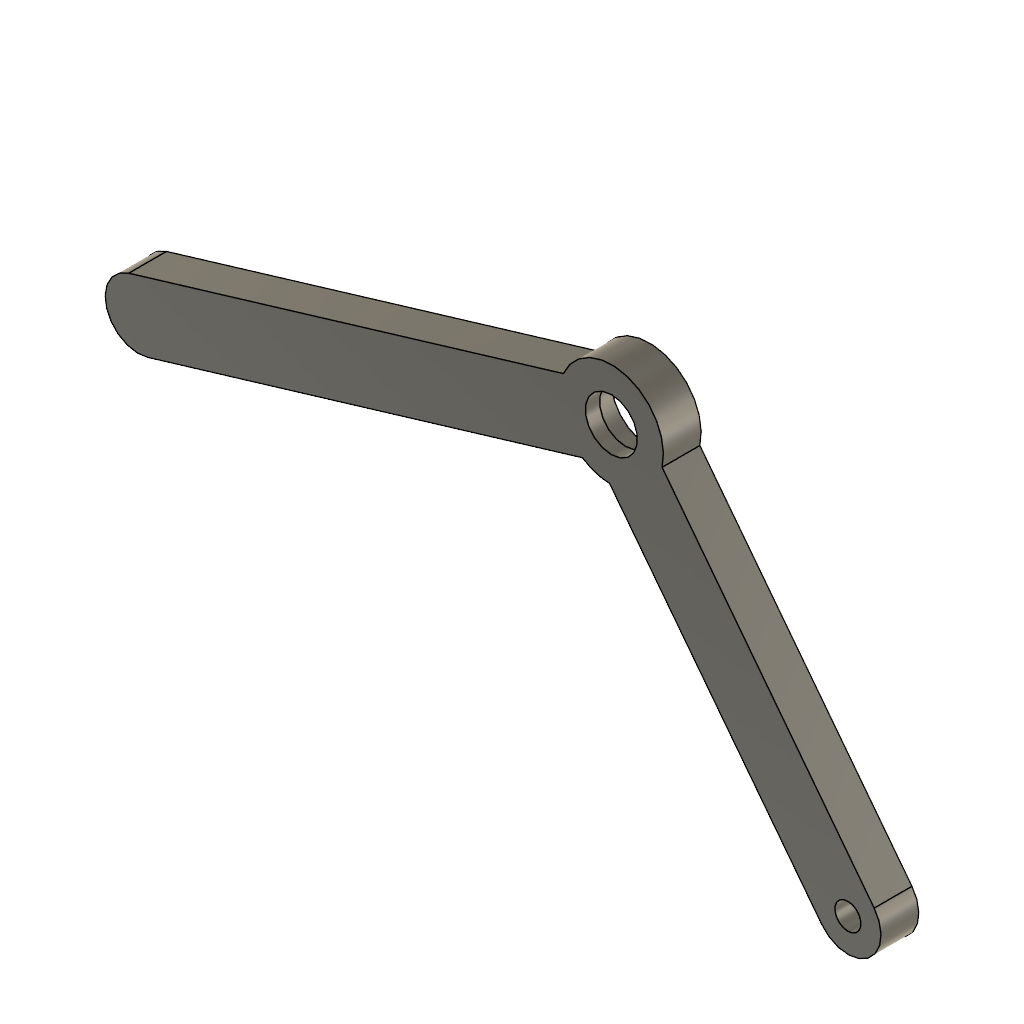
Rover V2 (Autodesk Fusion 360 archive; units mm, degrees)
design "Rocker_L"
part number: 2026-11-11-20-07-56-391
Autodesk Fusion 360 part; units mm, degrees
derive "DerivedContext1"
sketch "Rocker profile" plane through (0, 72, 0) normal (0, 1, 0) x (1, 0, 0)
  line L0 (-30, 0) -> (30, 0)
  line L1 (94.4516, -25.732) -> (44.4516, -90.732)
  arc A0 (44.4516, -90.732) -> (55.5484, -99.268) centre (50, -95) ccw
  line L2 (55.5484, -99.268) -> (105.5484, -34.268)
  arc A1 (105.5484, -34.268) -> (94.4516, -25.732) centre (100, -30) ccw
  line L3 (100, -30) -> (50, -95) construction
  line L4 (-52.0114, -71.7048) -> (47.9886, -101.7048)
  arc A2 (47.9886, -101.7048) -> (52.0114, -88.2952) centre (50, -95) ccw
  line L5 (52.0114, -88.2952) -> (-47.9886, -58.2952)
  arc A3 (-47.9886, -58.2952) -> (-52.0114, -71.7048) centre (-50, -65) ccw
  line L6 (-50, -65) -> (50, -95) construction
  circle A4 centre (50, -95) radius 11
  point P0 (100, -30)
  point P1 (50, -95)
  point P2 (-50, -65)
  dimension "d1" = 30
  dimension "d9" = 100
  dimension "d10" = 95
  dimension "d11" = 50
  dimension "d12" = 50
  dimension "d13" = 65
  dimension "d18" = 14
  dimension "d19" = 14
  dimension "d20" = 22
  constraint tangent L1 A0
  constraint tangent A0 L2
  constraint parallel L1 L2
  constraint tangent L2 A1
  constraint tangent L1 A1
  constraint coincident P1 A0.centre
  constraint coincident P0 A1.centre
  constraint tangent L4 A2
  constraint tangent A2 L5
  constraint parallel L4 L5
  constraint tangent L5 A3
  constraint tangent L4 A3
  constraint coincident P2 A3.centre
  constraint concentric A2 A4
  measures "d1" distance of P0 L0
  measures "d9" horizontal distance of P0 origin
  measures "d10" vertical distance of P1 origin
  measures "d11" horizontal distance of P1 origin
  measures "d12" horizontal distance of P2 origin
  measures "d13" vertical distance of P2 origin
  measures "d18" diameter of A0
  measures "d19" diameter of A2
  measures "d20" diameter of A4
extrude "Extrude1" add sketch "Rocker profile" along normal blind 8
hole "Hole1" at (50, 80, 95) direction (0, -1, 0) diameter 11 end through all counterbore diameter 16.1 counterbore depth 5
hole "Hole2" at (100, 72, 30) direction (0, 1, 0) diameter 5.5 end through all
equation "d1 = wheel_d / 2"
equation "wheel_d = 60 mm" comment "Axle height"
equation "wheel_pitch = 100 mm" comment "Front axle position, bogie position"
equation "rocker_pivot_x = 50 mm" comment "Rocker pivot position"
equation "rocker_pivot_h = 65 mm" comment "Rocker pivot height"
equation "bogie_pivot_h = 35 mm" comment "Bogie pivot height"
equation "body_w = 140 mm" comment "Arm plane"
equation "arm_gap = 2 mm" comment "Arm plane"
equation "d9 = wheel_pitch"
equation "d10 = wheel_d / 2 + rocker_pivot_h"
equation "d11 = rocker_pivot_x"
equation "d12 = wheel_pitch / 2"
equation "d13 = wheel_d / 2 + bogie_pivot_h"
equation "arm_w = 14 mm" comment "Arm width"
equation "pivot_bearing_od = 16 mm" comment "625ZZ outer diameter"
equation "boss_wall = 3 mm" comment "Material around bearing"
equation "boss_d = pivot_bearing_od + 2 * boss_wall" comment "Pivot boss diameter, 22 mm"
equation "d18 = arm_w"
equation "d19 = arm_w"
equation "d20 = boss_d"
equation "arm_t = 8 mm" comment "Arm thickness"
equation "d22 = arm_t"
equation "bearing_lip_d = 11 mm"
equation "fit_seat = 0.1 mm"
equation "fit_clear = 0.5 mm"
equation "pivot_bearing_w = 5 mm"
equation "d29 = bearing_lip_d"
equation "pivot_bore = 5 mm"
equation "d32 = pivot_bore + fit_clear"
equation "d34 = pivot_bearing_w"
equation "d35 = pivot_bearing_od + fit_seat"
named bodies: "Rocker_L"

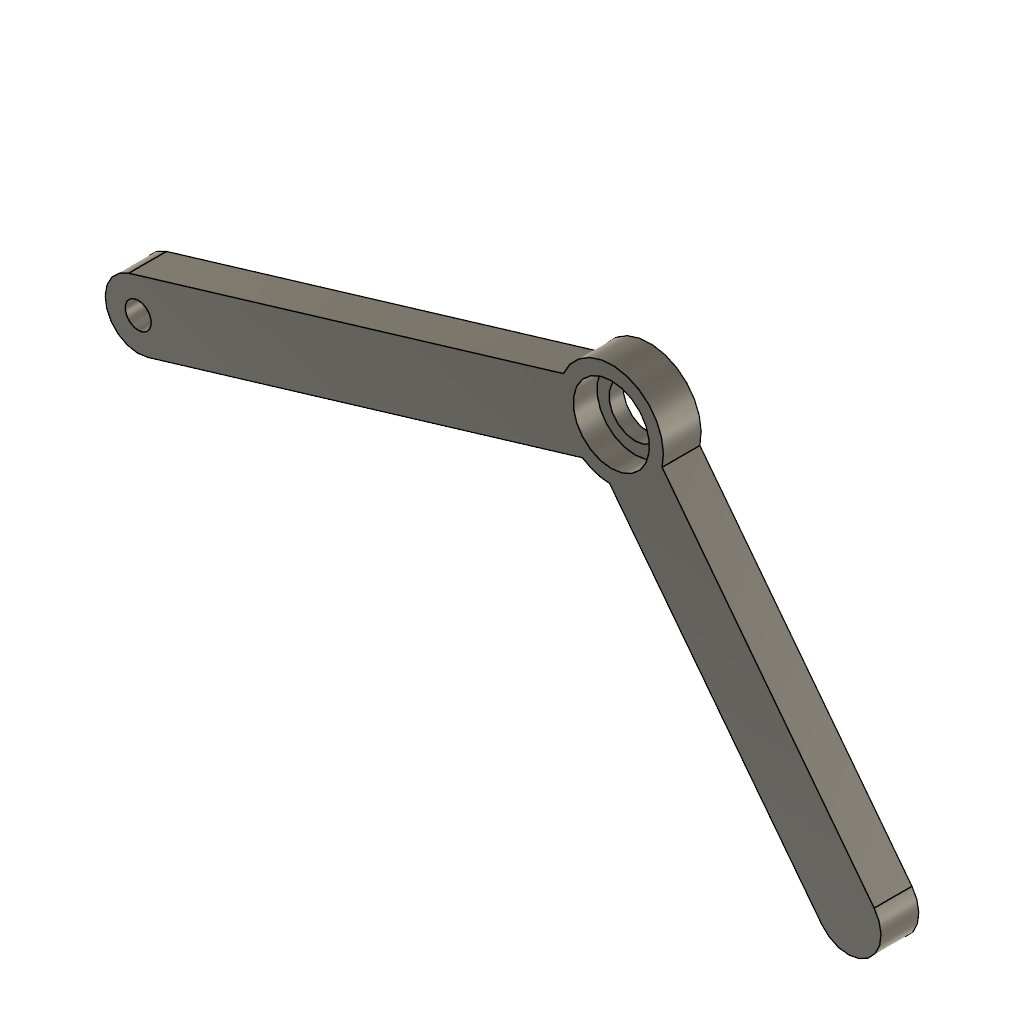
design "Rocker_R"
part number: 2026-11-13-20-06-45-332
Autodesk Fusion 360 part; units mm, degrees
derive "DerivedContext1"
sketch "Sketch1" plane through (0, -72, 0) normal (0, 1, 0) x (1, 0, 0)
sketch "Rocker profile" plane through (0, -72, 0) normal (0, 1, 0) x (1, 0, 0)
  line L0 (94.4516, -25.732) -> (44.4516, -90.732)
  arc A0 (44.4516, -90.732) -> (55.5484, -99.268) centre (50, -95) ccw
  line L1 (55.5484, -99.268) -> (105.5484, -34.268)
  arc A1 (105.5484, -34.268) -> (94.4516, -25.732) centre (100, -30) ccw
  line L2 (100, -30) -> (50, -95) construction
  line L3 (52.0114, -88.2952) -> (-47.9886, -58.2952)
  arc A2 (-47.9886, -58.2952) -> (-52.0114, -71.7048) centre (-50, -65) ccw
  line L4 (-52.0114, -71.7048) -> (47.9886, -101.7048)
  arc A3 (47.9886, -101.7048) -> (52.0114, -88.2952) centre (50, -95) ccw
  line L5 (50, -95) -> (-50, -65) construction
  circle A4 centre (50, -95) radius 11
  point P0 (100, -30)
  point P1 (50, -95)
  point P2 (-50, -65)
  dimension "d16" = 100
  dimension "d17" = 30
  dimension "d18" = 50
  dimension "d19" = 95
  dimension "d20" = 50
  dimension "d21" = 65
  dimension "d22" = 14
  dimension "d23" = 14
  dimension "d24" = 22
  constraint tangent L0 A0
  constraint tangent A0 L1
  constraint parallel L0 L1
  constraint tangent L1 A1
  constraint tangent L0 A1
  constraint coincident P1 A0.centre
  constraint coincident P0 A1.centre
  constraint tangent L3 A2
  constraint tangent A2 L4
  constraint parallel L3 L4
  constraint tangent L4 A3
  constraint tangent L3 A3
  constraint coincident P2 A2.centre
  constraint concentric A3 A4
  measures "d16" horizontal distance of P0 origin
  measures "d17" vertical distance of P0 origin
  measures "d18" horizontal distance of P1 origin
  measures "d19" vertical distance of P1 origin
  measures "d20" horizontal distance of P2 origin
  measures "d21" vertical distance of P2 origin
  measures "d22" diameter of A0
  measures "d23" diameter of A2
  measures "d24" diameter of A4
extrude "Extrude1" add sketch "Rocker profile" against normal blind 8
hole "Hole1" at (50, -80, 95) direction (0, 1, 0) diameter 11 end through all counterbore diameter 16.1 counterbore depth 5
hole "Hole2" at (-50, -80, 65) direction (0, 1, 0) diameter 5.5 end through all
equation "wheel_d = 60 mm"
equation "wheel_pitch = 100 mm"
equation "rocker_pivot_x = 50 mm"
equation "rocker_pivot_h = 65 mm"
equation "bogie_pivot_h = 35 mm"
equation "arm_w = 14 mm"
equation "arm_t = 8 mm"
equation "pivot_bore = 5 mm"
equation "pivot_bearing_od = 16 mm"
equation "pivot_bearing_w = 5 mm"
equation "boss_wall = 3 mm"
equation "boss_d = pivot_bearing_od + 2 * boss_wall"
equation "bearing_lip_d = 11 mm"
equation "fit_seat = 0.1 mm"
equation "fit_clear = 0.5 mm"
equation "d16 = wheel_pitch"
equation "d17 = wheel_d / 2"
equation "d18 = rocker_pivot_x"
equation "d19 = rocker_pivot_h + wheel_d / 2"
equation "d20 = wheel_pitch / 2"
equation "d21 = wheel_d / 2 + bogie_pivot_h"
equation "d22 = arm_w"
equation "d23 = arm_w"
equation "d24 = boss_d"
equation "d25 = -arm_t"
equation "d27 = bearing_lip_d"
equation "d29 = pivot_bearing_w"
equation "d30 = pivot_bearing_od + fit_seat"
equation "d32 = pivot_bore + fit_clear"
named bodies: "Rocker_R"
